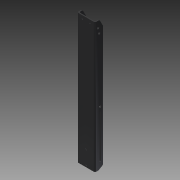
# Autodesk Inventor part: base
Saved by Autodesk Inventor 2015 (Build 190159000, 159)
## iProperties
Created: 2022-11-04
Part Number: base
Material: Generic
Document SubType Name: Modeling
Designer: Pavel Brodský
Density: 1 g/cm^3
Appearance: Default
Author: Pavel Brodský
Autodesk Inventor part; units mm, degrees
ref_plane "YZ Plane" through (0, 0, 0) normal (1, 0, 0) x (0, 1, 0)
ref_plane "XZ Plane" through (0, 0, 0) normal (0, 1, 0) x (-1, 0, 0)
ref_plane "XY Plane" through (0, 0, 0) normal (0, 0, 1) x (1, 0, 0)
sketch "Náčrt1" plane through (0, 0, 0) normal (0, 0, 1) x (1, 0, 0)
  line L0 (0, 30) -> (0, 0)
  line L1 (0, 0) -> (68, 0)
  line L2 (68, 0) -> (68, 30)
  line L3 (68, 30) -> (64, 30)
  line L4 (64, 30) -> (64, 4)
  line L5 (64, 4) -> (4, 4)
  line L6 (4, 4) -> (4, 30)
  line L7 (4, 30) -> (0, 30)
  dimension "d0" = 4
  dimension "d1" = 4
  dimension "d2" = 4
  dimension "d3" = 68
  dimension "d4" = 30
  constraints: 16 end point, 7 perpendicular, 1 point on line, 1 vertical
  measures "d0" distance of L2.end L3.end
  measures "d1" distance of L6.end L0.start
  measures "d2" distance between parallel lines of L1 L5
  measures "d3" distance of L0.end L1.end
  measures "d4" distance of L0.start L0.end
extrude "Vysunutí1" add sketch "Náčrt1" along normal blind 490
sketch "Náčrt2" plane through (68, 0, 0) normal (1, 0, 0) x (0, 0, -1)
  line L0 (0, 30) -> (-490, 30) projected
  line L1 (-465, 30) -> (-490, 17)
  line L2 (-490, 4) -> (-490, 30) projected
  line L3 (-490, 30) -> (-465, 30)
  line L4 (-490, 30) -> (-490, 17)
  line L5 (0, 13) -> (-10, 30)
  line L6 (0, 30) -> (-490, 30) projected
  line L7 (-10, 30) -> (0, 30)
  line L8 (0, 30) -> (0, 13)
  line L9 (0, 30) -> (0, 4) projected
  circle A0 centre (-466, 12) radius 4
  circle A1 centre (-447, 16) radius 4
  circle A2 centre (-205, 20) radius 4
  arc A3 (-187.5, 22) -> (-187.5, 17) centre (-187.5, 19.5) ccw
  arc A4 (-27.5, 17) -> (-27.5, 22) centre (-27.5, 19.5) ccw
  line L10 (-187.5, 17) -> (-27.5, 17)
  line L11 (-27.5, 22) -> (-187.5, 22)
  point P0 (0, 0)
  dimension "d7" = 25
  dimension "d10" = 10
  dimension "d11" = 13
  dimension "d12" = 8
  dimension "d13" = 24
  dimension "d14" = 8
  dimension "d15" = 43
  dimension "d16" = 12
  dimension "d17" = 8
  dimension "d18" = 285
  dimension "d19" = 16
  dimension "d20" = 8
  dimension "d21" = 2.5
  dimension "d22" = 2.5
  dimension "d23" = 27.5
  dimension "d24" = 302.5
  dimension "d25" = 15.5
  constraints: 17 end point, 6 point on circle, 5 centre point, 4 point on line, 3 collinear, 3 tangent, 1 horizontal alignment, 1 midpoint, 1 perpendicular, 1 vertical alignment
  measures "d7" distance of L0.end L1.start
  measures "d10" distance of L0.start L5.end
  measures "d11" distance of point (0, 0) L5.start
  measures "d12" vertical distance of L2.start A0.centre
  measures "d13" distance from line of L2 A0.centre
  measures "d14" diameter of A0
  measures "d15" horizontal distance of L1.end A1.centre
  measures "d16" vertical distance of L2.start A1.centre
  measures "d17" diameter of A1
  measures "d18" distance from line of L2 A2.centre
  measures "d19" vertical distance of L2.start A2.centre
  measures "d20" diameter of A2
  measures "d21" radius of A3
  measures "d22" radius of A4
  measures "d23" distance from line of L9 A4.centre
  measures "d24" distance from line of L2 A3.centre
  measures "d25" vertical distance of L2.start A3.centre
extrude "Vysunutí2" cut sketch "Náčrt2" against normal through all
fillet "Zaoblení1" radius 5 12 edges at (2, 30, 465) (66, 30, 465) (2, 17, 490) (66, 17, 490) (66, 30, 10) (66, 13, 0) (2, 30, 10) (2, 13, 0) (68, 0, 245) (0, 0, 245) (4, 4, 245) (64, 4, 245)
sketch "Náčrt3" plane through (9, 4, 0) normal (0, 1, 0) x (1, 0, 0)
  circle A0 centre (25, -7) radius 2.5
  circle A1 centre (25, -58) radius 2.5
  circle A2 centre (11, -478) radius 2.5
  circle A3 centre (39, -478) radius 2.5
  line L0 (0, 0) -> (50, 0) projected
  line L1 (-9, -12.8597) -> (-9, -463.7777) projected
  line L2 (59, -12.8597) -> (59, -463.7777) projected
  line L3 (-9, -8.5501) -> (-9, -0.6903) projected
  line L4 (50, -490) -> (0, -490) projected
  line L5 (-9, -487.3068) -> (-9, -466.0845) projected
  point P0 (-9, 0)
  dimension "d28" = 5
  dimension "d29" = 5
  dimension "d30" = 5
  dimension "d31" = 5
  dimension "d32" = 7
  dimension "d33" = 58
  dimension "d34" = 34
  dimension "d35" = 68
  dimension "d36" = 34
  dimension "d37" = 12
  dimension "d38" = 12
  dimension "d39" = 28
  dimension "d40" = 20
  constraints: 4 centre point
  measures "d28" diameter of A1
  measures "d29" diameter of A0
  measures "d30" diameter of A2
  measures "d31" diameter of A3
  measures "d32" distance from line of L0 A0.centre
  measures "d33" distance from line of A1.centre L0
  measures "d34" distance from line of L1 A1.centre
  measures "d35" distance between parallel lines of L2 L1
  measures "d36" distance from line of A0.centre L3
  measures "d37" distance from line of L4 A2.centre
  measures "d38" distance from line of L4 A3.centre
  measures "d39" distance of A3.centre A2.centre
  measures "d40" distance from line of L5 A2.centre
extrude "Vysunutí3" cut sketch "Náčrt3" against normal through all
equation "\"d1\" = d0"
equation "\"d2\" = d0"
equation "\"d22\" = d21"
equation "\"d29\" = d28"
equation "\"d31\" = d30"
equation "\"d34\" = 0.5 * d35"
equation "\"d36\" = 0.5 * d35"
equation "\"d38\" = d37"
equation "\"d40\" = 0.5 * d35 - 0.5 * d39"
